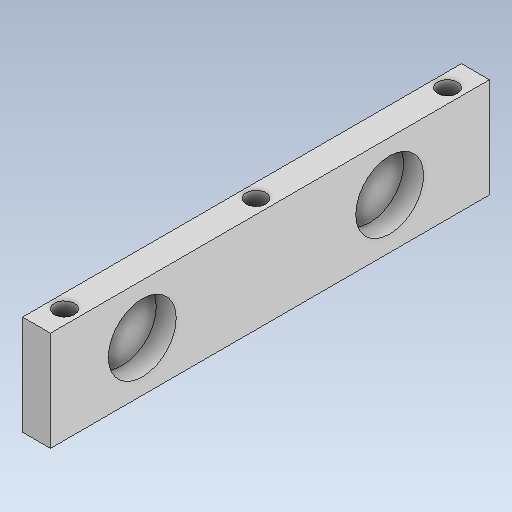
# Autodesk Inventor part: Seitenteil_außen
Saved by Autodesk Inventor 2026.4 (Build 304435000, 435)
## iProperties
Created: 2026-11-13
Part Number: Seitenteil_außen
Material: Generisch
Document SubType Name: Modeling
Designer: weira
Density: 1 g/cm^3
Appearance: Vorgabe
Mass: 28.5302 g
Surface Area: 114.341 cm^2
Volume: 28.5302 cm^3
Author: weira
Autodesk Inventor part; units mm, degrees
ref_plane "YZ Plane" through (0, 0, 0) normal (1, 0, 0) x (0, 1, 0)
ref_plane "XZ Plane" through (0, 0, 0) normal (0, 1, 0) x (-1, 0, 0)
ref_plane "XY Plane" through (0, 0, 0) normal (0, 0, 1) x (1, 0, 0)
sketch "Skizze1" plane through (0, 0, 0) normal (1, 0, 0) x (0, 1, 0)
  line L0 (55, -12.5) -> (-55, -12.5)
  line L1 (-55, -12.5) -> (-55, 12.5)
  line L2 (-55, 12.5) -> (55, 12.5)
  line L3 (55, 12.5) -> (55, -12.5)
  line L4 (55, -12.5) -> (-55, 12.5) construction
  line L5 (-55, -12.5) -> (55, 12.5) construction
  circle A0 centre (-32, 0) radius 8.5
  circle A1 centre (30, 0) radius 8.5
  point P0 (0, 0)
  dimension "d0" = 25
  dimension "d5" = 110
  dimension "d6" = 23
  dimension "d7" = 62
  dimension "d8" = 17
  dimension "d9" = 17
  dimension "d10" = 12.5
  dimension "d11" = 12.5
  constraints: 12 end point, 2 centre point, 2 midpoint, 2 parallel, 1 horizontal, 1 perpendicular
  measures "d0" distance between parallel lines of L0 L2
  measures "d5" distance of L1.end L2.end
  measures "d6" distance from line of L1 A0.centre
  measures "d7" distance of A1.centre A0.centre
  measures "d8" diameter of A0
  measures "d9" diameter of A1
  measures "d10" distance from line of L2 A0.centre
  measures "d11" distance from line of L2 A1.centre
extrude "Extrusion1" add sketch "Skizze1" against normal blind 7 contours L0 L1 L2 L3 | A0 | A1
extrude "Extrusion2" cut sketch "Skizze1" against normal blind 5 contours A0 | A1
sketch "Skizze2" plane through (0, -55, 12.5) normal (0, 0, 1) x (1, 0, 0)
  line L0 (-7, 110) -> (-7, 0)
  line L1 (-7, 0) -> (0, 0)
  line L2 (0, 110) -> (0, 0)
  line L3 (-7, 110) -> (0, 110)
  line L4 (0, 110) -> (0, 0) projected
  line L5 (0, 110) -> (-7, 110) projected
  line L6 (-7, 0) -> (-7, 110) projected
  line L7 (0, 0) -> (-7, 0) projected
  point P0 (0, 55)
  point P1 (-7, 55)
  point P2 (-3.5, 103)
  point P3 (-3.5, 7)
  point P4 (-3.5, 55)
  dimension "d12" = 7
  dimension "d13" = 7
  dimension "d14" = 7
  dimension "d15" = 3.5
  dimension "d16" = 3.5
  dimension "d17" = 3.5
  dimension "d18" = 96
  dimension "d19" = 48
  constraints: 8 end point, 1 coincident
  measures "d12" distance from line of L3 point (-3.5, 103)
  measures "d13" distance between parallel lines of L0 L2
  measures "d14" distance from line of L1 point (-3.5, 7)
  measures "d15" distance from line of L0 point (-3.5, 7)
  measures "d16" distance from line of L0 point (-3.5, 103)
  measures "d17" distance from line of L0 point (-3.5, 55)
  measures "d18" distance of point (-3.5, 7) point (-3.5, 103)
  measures "d19" distance of point (-3.5, 103) point (-3.5, 55)
hole "Bohrung1" at (-3.5, 48, 12.5) at (-3.5, -48, 12.5) at (-3.5, 0, 12.5) direction (0, 0, -1) diameter 5 end through all
equation "\"d9\" = d8"
equation "\"d10\" = 0.5 * d0"
equation "\"d11\" = d10"
equation "\"d19\" = 0.5 * d18"
